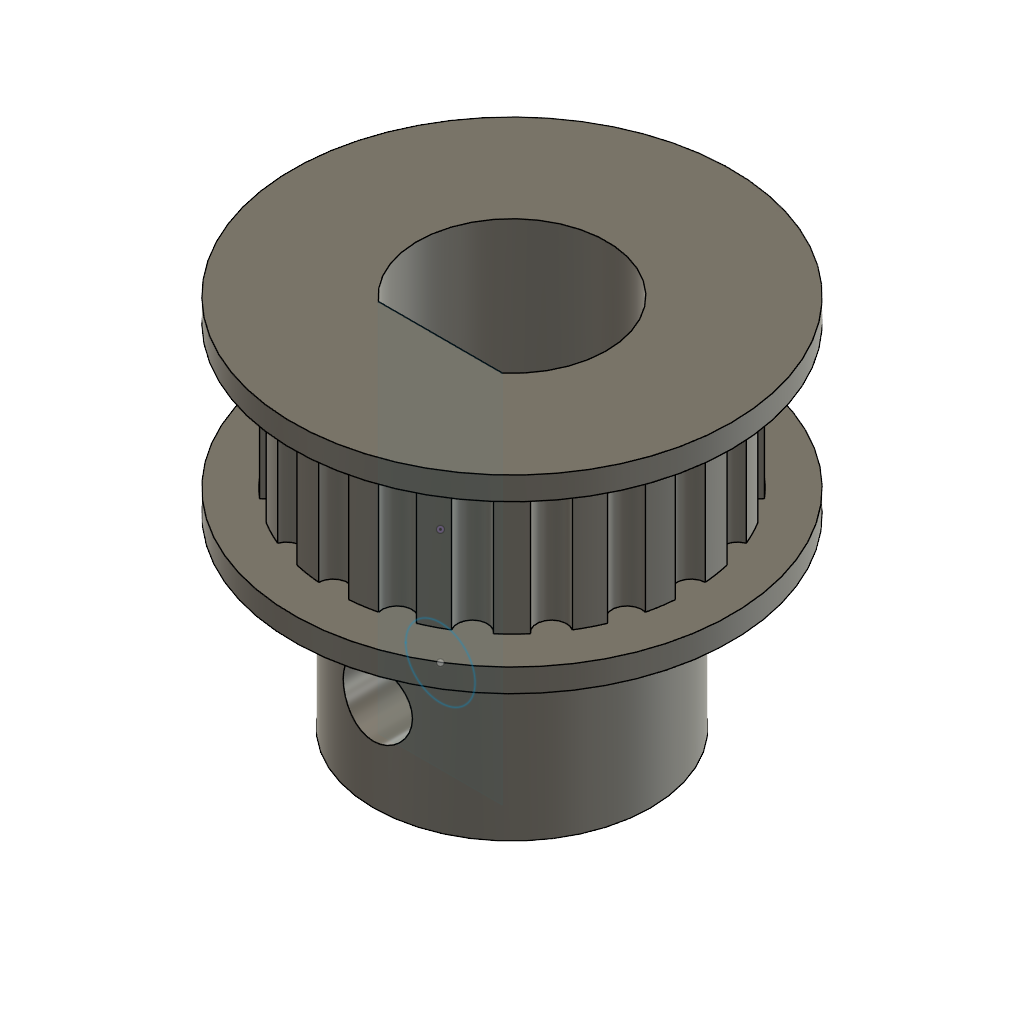
02-24_축풀리_20T (Autodesk Fusion 360 design; units mm, degrees)
Autodesk Fusion 360 part; units mm, degrees
sketch "스케치1" plane through (0, 0, 0) normal (0, 1, 0) x (1, 0, 0)
  circle A0 centre (0, 0) radius 7.75
  dimension "d1" = 15.5
  constraint coincident A0.centre origin
  measures "d1" diameter of A0
extrude "돌출1" add sketch "스케치1" along normal blind 6.2
sketch "스케치2" plane through (0, 6.2, 0) normal (0, 1, 0) x (-1, 0, 0)
  circle A0 centre (0, 0) radius 7.75
  circle A1 centre (-7.75, 0) radius 0.65
  circle A2 centre (-7.3707, -2.3949) radius 0.65
  circle A3 centre (-6.2699, -4.5553) radius 0.65
  circle A4 centre (-4.5553, -6.2699) radius 0.65
  circle A5 centre (-2.3949, -7.3707) radius 0.65
  circle A6 centre (0, -7.75) radius 0.65
  circle A7 centre (2.3949, -7.3707) radius 0.65
  circle A8 centre (4.5553, -6.2699) radius 0.65
  circle A9 centre (6.2699, -4.5553) radius 0.65
  circle A10 centre (7.3707, -2.3949) radius 0.65
  circle A11 centre (7.75, 0) radius 0.65
  circle A12 centre (7.3707, 2.3949) radius 0.65
  circle A13 centre (6.2699, 4.5553) radius 0.65
  circle A14 centre (4.5553, 6.2699) radius 0.65
  circle A15 centre (2.3949, 7.3707) radius 0.65
  circle A16 centre (0, 7.75) radius 0.65
  circle A17 centre (-2.3949, 7.3707) radius 0.65
  circle A18 centre (-4.5553, 6.2699) radius 0.65
  circle A19 centre (-6.2699, 4.5553) radius 0.65
  circle A20 centre (-7.3707, 2.3949) radius 0.65
  dimension "d4" = 1.3
  dimension "d6" = 360
  constraint coincident A0 A1.centre
  measures "d4" diameter of A1
extrude "돌출2" cut sketch "스케치2" against normal blind 6.2 contours A0 A11 | A0 A12 | A0 A10 | A0 A13 | A0 A9 | A0 A14 | A0 A8 | A0 A15 | A0 A7 | A0 A16 | A0 A6 | A0 A17 | A0 A5 | A0 A18 | A0 A4 | A0 A19 | A0 A3 | A0 A20 | A0 A2 | A0 A1 picked at (7.5465, 0.1494) picked at (7.1584, 2.3425) picked at (7.1584, -2.3425) picked at (6.0842, 4.4399) picked at (6.0842, -4.4399) picked at (4.4399, 6.0842) picked at (4.4399, -6.0842) picked at (2.3125, 7.1681) picked at (2.3425, -7.1584) picked at (0.0158, 7.5319) picked at (-0.0158, -7.5319) picked at (-2.3404, 7.1589) picked at (-2.3404, -7.1589) picked at (-4.4148, 6.1023) picked at (-4.4148, -6.1023) picked at (-6.0865, 4.4363) picked at (-6.0865, -4.4363) picked at (-7.1608, 2.3336) picked at (-7.1608, -2.3336) picked at (-7.5313, 0)
sketch "스케치3" plane through (0, 6.2, 0) normal (0, 1, 0) x (-1, 0, 0)
  arc A0 (6.6296, -4.0139) -> (5.8661, -5.0647) centre (6.2699, -4.5553) ccw
  arc A1 (6.6296, -4.0139) -> (7.1441, -3.0041) centre (0, 0) ccw
  arc A2 (7.5454, -1.7688) -> (7.1441, -3.0041) centre (7.3707, -2.3949) ccw
  arc A3 (7.5454, -1.7688) -> (7.7227, -0.6494) centre (0, 0) ccw
  arc A4 (7.7227, 0.6494) -> (7.7227, -0.6494) centre (7.75, 0) ccw
  arc A5 (7.7227, 0.6494) -> (7.5454, 1.7688) centre (0, 0) ccw
  arc A6 (7.1441, 3.0041) -> (7.5454, 1.7688) centre (7.3707, 2.3949) ccw
  arc A7 (7.1441, 3.0041) -> (6.6296, 4.0139) centre (0, 0) ccw
  arc A8 (5.8661, 5.0647) -> (6.6296, 4.0139) centre (6.2699, 4.5553) ccw
  arc A9 (5.8661, 5.0647) -> (5.0647, 5.8661) centre (0, 0) ccw
  arc A10 (4.0139, 6.6296) -> (5.0647, 5.8661) centre (4.5553, 6.2699) ccw
  arc A11 (4.0139, 6.6296) -> (3.0041, 7.1441) centre (0, 0) ccw
  arc A12 (1.7688, 7.5454) -> (3.0041, 7.1441) centre (2.3949, 7.3707) ccw
  arc A13 (1.7688, 7.5454) -> (0.6494, 7.7227) centre (0, 0) ccw
  arc A14 (-0.6494, 7.7227) -> (0.6494, 7.7227) centre (0, 7.75) ccw
  arc A15 (-0.6494, 7.7227) -> (-1.7688, 7.5454) centre (0, 0) ccw
  arc A16 (-3.0041, 7.1441) -> (-1.7688, 7.5454) centre (-2.3949, 7.3707) ccw
  arc A17 (-3.0041, 7.1441) -> (-4.0139, 6.6296) centre (0, 0) ccw
  arc A18 (-5.0647, 5.8661) -> (-4.0139, 6.6296) centre (-4.5553, 6.2699) ccw
  arc A19 (-5.0647, 5.8661) -> (-5.8661, 5.0647) centre (0, 0) ccw
  arc A20 (-6.6296, 4.0139) -> (-5.8661, 5.0647) centre (-6.2699, 4.5553) ccw
  arc A21 (-6.6296, 4.0139) -> (-7.1441, 3.0041) centre (0, 0) ccw
  arc A22 (-7.5454, 1.7688) -> (-7.1441, 3.0041) centre (-7.3707, 2.3949) ccw
  arc A23 (-7.5454, 1.7688) -> (-7.7227, 0.6494) centre (0, 0) ccw
  arc A24 (-7.7227, -0.6494) -> (-7.7227, 0.6494) centre (-7.75, 0) ccw
  arc A25 (-7.7227, -0.6494) -> (-7.5454, -1.7688) centre (0, 0) ccw
  arc A26 (-7.1441, -3.0041) -> (-7.5454, -1.7688) centre (-7.3707, -2.3949) ccw
  arc A27 (-7.1441, -3.0041) -> (-6.6296, -4.0139) centre (0, 0) ccw
  arc A28 (-5.8661, -5.0647) -> (-6.6296, -4.0139) centre (-6.2699, -4.5553) ccw
  arc A29 (-5.8661, -5.0647) -> (-5.0647, -5.8661) centre (0, 0) ccw
  arc A30 (-4.0139, -6.6296) -> (-5.0647, -5.8661) centre (-4.5553, -6.2699) ccw
  arc A31 (-4.0139, -6.6296) -> (-3.0041, -7.1441) centre (0, 0) ccw
  arc A32 (-1.7688, -7.5454) -> (-3.0041, -7.1441) centre (-2.3949, -7.3707) ccw
  arc A33 (-1.7688, -7.5454) -> (-0.6494, -7.7227) centre (0, 0) ccw
  arc A34 (0.6494, -7.7227) -> (-0.6494, -7.7227) centre (0, -7.75) ccw
  arc A35 (0.6494, -7.7227) -> (1.7688, -7.5454) centre (0, 0) ccw
  arc A36 (3.0041, -7.1441) -> (1.7688, -7.5454) centre (2.3949, -7.3707) ccw
  arc A37 (3.0041, -7.1441) -> (4.0139, -6.6296) centre (0, 0) ccw
  arc A38 (5.0647, -5.8661) -> (4.0139, -6.6296) centre (4.5553, -6.2699) ccw
  arc A39 (5.0647, -5.8661) -> (5.8661, -5.0647) centre (0, 0) ccw
  circle A40 centre (0, 0) radius 9.5
  dimension "d9" = 19
  constraint coincident A1.centre A3.centre
  measures "d9" diameter of A40
extrude "돌출3" add sketch "스케치3" along normal blind 1 contours A0 A1 A2 A3 A4 A5 A6 A7 A8 A9 A10 A11 A12 A13 A14 A15 A16 A17 A18 A19 A20 A21 A22 A23 A24 A25 A26 A27 A28 A29 A30 A31 A32 A33 A34 A35 A36 A37 A38 A39 | A40
sketch "스케치4" plane through (0, 0, 0) normal (0, -1, 0) x (1, 0, 0)
  arc A0 (-5.8661, -5.0647) -> (-6.6296, -4.0139) centre (-6.2699, -4.5553) ccw
  arc A1 (-5.8661, -5.0647) -> (-5.0647, -5.8661) centre (0, 0) ccw
  arc A2 (-4.0139, -6.6296) -> (-5.0647, -5.8661) centre (-4.5553, -6.2699) ccw
  arc A3 (-4.0139, -6.6296) -> (-3.0041, -7.1441) centre (0, 0) ccw
  arc A4 (-1.7688, -7.5454) -> (-3.0041, -7.1441) centre (-2.3949, -7.3707) ccw
  arc A5 (-1.7688, -7.5454) -> (-0.6494, -7.7227) centre (0, 0) ccw
  arc A6 (0.6494, -7.7227) -> (-0.6494, -7.7227) centre (0, -7.75) ccw
  arc A7 (0.6494, -7.7227) -> (1.7688, -7.5454) centre (0, 0) ccw
  arc A8 (3.0041, -7.1441) -> (1.7688, -7.5454) centre (2.3949, -7.3707) ccw
  arc A9 (3.0041, -7.1441) -> (4.0139, -6.6296) centre (0, 0) ccw
  arc A10 (5.0647, -5.8661) -> (4.0139, -6.6296) centre (4.5553, -6.2699) ccw
  arc A11 (5.0647, -5.8661) -> (5.8661, -5.0647) centre (0, 0) ccw
  arc A12 (6.6296, -4.0139) -> (5.8661, -5.0647) centre (6.2699, -4.5553) ccw
  arc A13 (6.6296, -4.0139) -> (7.1441, -3.0041) centre (0, 0) ccw
  arc A14 (7.5454, -1.7688) -> (7.1441, -3.0041) centre (7.3707, -2.3949) ccw
  arc A15 (7.5454, -1.7688) -> (7.7227, -0.6494) centre (0, 0) ccw
  arc A16 (7.7227, 0.6494) -> (7.7227, -0.6494) centre (7.75, 0) ccw
  arc A17 (7.7227, 0.6494) -> (7.5454, 1.7688) centre (0, 0) ccw
  arc A18 (7.1441, 3.0041) -> (7.5454, 1.7688) centre (7.3707, 2.3949) ccw
  arc A19 (7.1441, 3.0041) -> (6.6296, 4.0139) centre (0, 0) ccw
  arc A20 (5.8661, 5.0647) -> (6.6296, 4.0139) centre (6.2699, 4.5553) ccw
  arc A21 (5.8661, 5.0647) -> (5.0647, 5.8661) centre (0, 0) ccw
  arc A22 (4.0139, 6.6296) -> (5.0647, 5.8661) centre (4.5553, 6.2699) ccw
  arc A23 (4.0139, 6.6296) -> (3.0041, 7.1441) centre (0, 0) ccw
  arc A24 (1.7688, 7.5454) -> (3.0041, 7.1441) centre (2.3949, 7.3707) ccw
  arc A25 (1.7688, 7.5454) -> (0.6494, 7.7227) centre (0, 0) ccw
  arc A26 (-0.6494, 7.7227) -> (0.6494, 7.7227) centre (0, 7.75) ccw
  arc A27 (-0.6494, 7.7227) -> (-1.7688, 7.5454) centre (0, 0) ccw
  arc A28 (-3.0041, 7.1441) -> (-1.7688, 7.5454) centre (-2.3949, 7.3707) ccw
  arc A29 (-3.0041, 7.1441) -> (-4.0139, 6.6296) centre (0, 0) ccw
  arc A30 (-5.0647, 5.8661) -> (-4.0139, 6.6296) centre (-4.5553, 6.2699) ccw
  arc A31 (-5.0647, 5.8661) -> (-5.8661, 5.0647) centre (0, 0) ccw
  arc A32 (-6.6296, 4.0139) -> (-5.8661, 5.0647) centre (-6.2699, 4.5553) ccw
  arc A33 (-6.6296, 4.0139) -> (-7.1441, 3.0041) centre (0, 0) ccw
  arc A34 (-7.5454, 1.7688) -> (-7.1441, 3.0041) centre (-7.3707, 2.3949) ccw
  arc A35 (-7.5454, 1.7688) -> (-7.7227, 0.6494) centre (0, 0) ccw
  arc A36 (-7.7227, -0.6494) -> (-7.7227, 0.6494) centre (-7.75, 0) ccw
  arc A37 (-7.7227, -0.6494) -> (-7.5454, -1.7688) centre (0, 0) ccw
  arc A38 (-7.1441, -3.0041) -> (-7.5454, -1.7688) centre (-7.3707, -2.3949) ccw
  arc A39 (-7.1441, -3.0041) -> (-6.6296, -4.0139) centre (0, 0) ccw
  circle A40 centre (0, 0) radius 9.5
  dimension "d12" = 19
  constraint concentric A1 A40
  measures "d12" diameter of A40
extrude "돌출4" add sketch "스케치4" along normal blind 1 contours A0 A1 A2 A3 A4 A5 A6 A7 A8 A9 A10 A11 A12 A13 A14 A15 A16 A17 A18 A19 A20 A21 A22 A23 A24 A25 A26 A27 A28 A29 A30 A31 A32 A33 A34 A35 A36 A37 A38 A39 | A40
sketch "스케치5" plane through (0, -1, 0) normal (0, -1, 0) x (1, 0, 0)
  circle A0 centre (0, 0) radius 9.5
  circle A1 centre (0, 0) radius 6
  dimension "d15" = 12
  constraint coincident A0.centre A1.centre
  measures "d15" diameter of A1
extrude "돌출5" add sketch "스케치5" along normal blind 8 contours A1
sketch "스케치6" plane through (0, -9, 0) normal (0, -1, 0) x (1, 0, 0)
  circle A0 centre (0, 0) radius 6
  line L0 (-2.6833, 3.1) -> (2.6833, 3.1)
  arc A1 (-2.6833, 3.1) -> (2.6833, 3.1) centre (0, 0) ccw
  dimension "d18" = 8.2
  dimension "d19" = 3.1
  constraint concentric A0 A1
  constraint horizontal L0
  measures "d18" diameter of A1
  measures "d19" distance of A0.centre L0
extrude "돌출6" cut sketch "스케치6" against normal blind 16.2 contours L0 A1
sketch "스케치7" plane through (0, 0, 3.1) normal (0, 0, -1) x (-1, 0, 0)
  line L0 (-2.6833, -9) -> (2.6833, -9)
  line L1 (2.6833, -9) -> (2.6833, 7.2)
  line L2 (2.6833, 7.2) -> (-2.6833, 7.2)
  line L3 (-2.6833, 7.2) -> (-2.6833, -9)
  circle A0 centre (0, -5) radius 1.5
  dimension "d22" = 3
  dimension "d23" = 5
  measures "d22" diameter of A0
  measures "d23" distance of origin A0.centre
extrude "돌출7" cut sketch "스케치7" against normal blind 3 contours A0
extrude "돌출8" cut sketch "스케치7" along normal blind 9.1 contours A0
